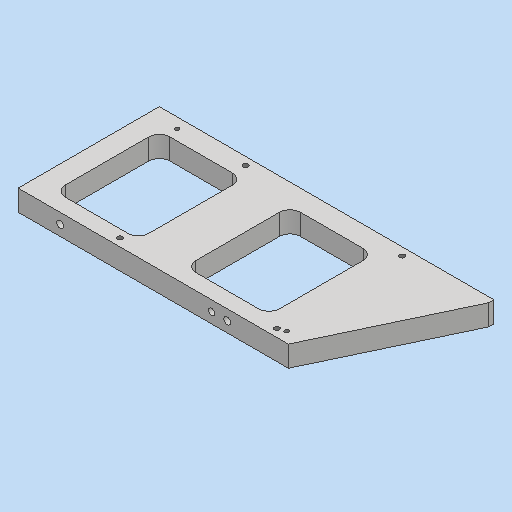
# Autodesk Inventor part: MM0948AN100_G01_155
Saved by Autodesk Inventor 2023.3 (Build 273359000, 359)
## iProperties
Part Number: MM0948AN100_G01_155
Material: 1.2842 90MnCrV8
Description: =<RBPARTNOTITLE2>
Document SubType Name: Modeling
Designer: ric7an
Mass: 3629.61 g
Surface Area: 811.162 cm^2
Volume: 462.37 cm^3
Density: 7.85 g/cm^3
Appearance: silber AnP
Created: 2023-03-23
RBDOCUMENTTYPE: DRF
RBDOCUMENTVERSION: 00
RBDRAWINGMAINSCALE: 1:1
RBDRAWINGMISSINGSPEC: --
RBDRAWINGVOLUME: --
RBGBEDGESIN1: +0,5
RBGBEDGESIN2: +0,2
RBGBEDGESOUT1: -0,3
RBGBEDGESOUT2: -0,1
RBMATERIAL: =<Material>
RBMATMEETS: --
RBMATNO: =<Part Number>
RBPARTMADEOF: 20 x 135 x 326,5 (FM)
RBPARTNO: SIEHE MNR
RBPARTNOTITLE1: manufactured part
RBPARTNOTITLE2: Anfertigungsteil
RBPARTSAFETYINDICATOR: --
RBSURFACE: chemically nickel-coated
RBSURFACE2: chem. vernickelt
RBZEDGESNORM: ISO13715:2002-06
RBZGENDIMCLASS: m
RBZGENDIMNORM: ISO 2768-1:1989-11
RBZGENGEOCLASS: H
RBZGENGEONORM: ISO 2768-2:1989-11
RBZSURFACENORM: ISO13D2:2002-02
RBZTOLERANCENORM: ISO 14405-1:2010-12
AnP_Material: =<Material>
AnP_TemplVers: 20190222
AnP_Kategorie: 1
MaxAbmaße: 20 x 135 x 326,5 (FM)
AnP_Kommentar_aktuell: =<Comments>
AnP_Material_aktuell: =<Material>
Author: FH/Wi
Keywords: =<RBPARTMADEOF>
Comments: =<RBSURFACE2>
Revision Number: 01
Autodesk Inventor part; units mm, degrees
ref_plane "YZ Plane" through (0, 0, 0) normal (1, 0, 0) x (0, 1, 0)
ref_plane "XZ Plane" through (0, 0, 0) normal (0, 1, 0) x (-1, 0, 0)
ref_plane "XY Plane" through (0, 0, 0) normal (0, 0, 1) x (1, 0, 0)
sketch "Skizze1" plane through (0, 0, 0) normal (0, 0, 1) x (1, 0, 0)
  line L0 (-160, 135) -> (160, 135)
  line L1 (160, 135) -> (160, 0)
  line L2 (160, 0) -> (-160, 0)
  line L3 (-160, 0) -> (-160, 135)
  line L4 (0, 162) -> (0, -27) projected
  line L5 (-224, 0) -> (224, 0) projected
  point P0 (0, 0)
  dimension "d0" = 135
  dimension "d1" = 320
  constraints: 8 end point, 2 parallel, 1 collinear, 1 horizontal, 1 perpendicular, 1 other
  measures "d0" distance of L0.end L1.end
  measures "d1" distance of L0.start L0.end
extrude "Extrusion1" add sketch "Skizze1" along normal mid plane 20
sketch "Skizze2" plane through (-160, 135, 10) normal (0, 1, 0) x (1, 0, 0)
  line L0 (160, 24) -> (160, -4) projected
  line L1 (384, 10) -> (-64, 10) projected
  line L2 (320, 0) -> (320, 20) projected
  line L3 (0, 20) -> (0, 0) projected
  point P0 (160, 10)
  point P1 (160, 10)
  point P2 (300, 10)
  dimension "d4" = 140
  dimension "d106" = 20
  constraints: 1 midpoint, 1 point on line
  measures "d4" distance of point (300, 10) point (160, 10)
  measures "d106" distance from line of L2 point (300, 10)
hole "Bohrung1" at (0, 135, 0) at (140, 135, 0) direction (0, -1, 0) diameter 4.917 depth 17.1 tip angle 118 thread size "M6x1" designation "M6" class "6H" standard "ISO Metric profile"
sketch "Skizze3" plane through (0, 0, 10) normal (0, 0, 1) x (1, 0, 0)
  line L0 (-15, 115) -> (65, 115)
  line L1 (65, 115) -> (65, 15)
  line L2 (65, 15) -> (-15, 15)
  line L3 (-15, 15) -> (-15, 115)
  line L4 (-160, 0) -> (160, 0) projected
  line L5 (-228.55, 0) -> (228.55, 0) projected
  line L6 (160, 0) -> (160, 135) projected
  line L7 (-160, 135) -> (-160, 0) projected
  line L8 (25, 115) -> (25, 15) construction
  line L9 (-140, 115) -> (-60, 115)
  line L10 (-60, 115) -> (-60, 15)
  line L11 (-60, 15) -> (-140, 15)
  line L12 (-140, 15) -> (-140, 115)
  line L13 (-100, 115) -> (-100, 15) construction
  point P0 (0, 0)
  dimension "d14" = 80
  dimension "d28" = 100
  dimension "d29" = 15
  dimension "d74" = 100
  dimension "d75" = 80
  dimension "d100" = 125
  dimension "d107" = 95
  constraints: 20 end point, 4 midpoint, 4 parallel, 2 horizontal, 2 perpendicular, 1 collinear
  measures "d14" distance of L0.start L0.end
  measures "d28" distance of L0.end L1.end
  measures "d29" distance between parallel lines of L4 L2
  measures "d74" distance of L9.end L10.end
  measures "d75" distance of L9.start L9.end
  measures "d100" distance between parallel lines of L3 L12
  measures "d107" distance between parallel lines of L6 L1
extrude "Extrusion2" cut sketch "Skizze3" against normal through all
sketch "Skizze4" plane through (-161.5, 15, 10) normal (0, -1, 0) x (1, 0, 0)
  line L0 (-62.5, -10) -> (385.5, -10) projected
  line L1 (226.5, 0) -> (146.5, 0) projected
  line L2 (21.5, -20) -> (101.5, -20) projected
  line L3 (21.5, 0) -> (21.5, -20) projected
  line L4 (101.5, 0) -> (21.5, 0) projected
  line L5 (101.5, 0) -> (101.5, -20) projected
  line L6 (321.5, 0) -> (321.5, -20) projected
  point P0 (161.5, -10)
  point P1 (201.5, -10)
  point P2 (41.5, -10)
  dimension "d109" = 160
  dimension "d110" = 120
  constraints: 2 point on line
  measures "d109" distance of point (201.5, -10) point (41.5, -10)
  measures "d110" distance from line of point (201.5, -10) L6
hole "Bohrung2" at (40, 15, 0) at (-120, 15, 0) direction (0, -1, 0) diameter 6.6 end through all clearance for "Innensechskant-Senkkopfschraube ISO 10642" size "M6" standard "ISO"
fillet "Rundung1" radius 10 8 edges at (-15, 115, 0) (65, 115, 0) (65, 15, 0) (-15, 15, 0) (-140, 15, 0) (-60, 15, 0) (-60, 115, 0) (-140, 115, 0)
sketch "Skizze8" plane through (0, 0, -10) normal (0, 0, -1) x (-1, 0, 0)
  line L0 (-160, 0) -> (160, 0) projected
  line L1 (-160, 135) -> (-160, 0) projected
  line L2 (160, 0) -> (160, 135) projected
  point P0 (-87, 10)
  point P1 (133, 125)
  dimension "d58" = 220
  dimension "d69" = 10
  dimension "d70" = 115
  dimension "d108" = 73
  measures "d58" horizontal distance of point (133, 125) point (-87, 10)
  measures "d69" distance from line of L0 point (-87, 10)
  measures "d70" vertical distance of point (133, 125) point (-87, 10)
  measures "d108" distance from line of point (-87, 10) L1
hole "Bohrung4" at (87, 10, -10) at (-133, 125, -10) direction (0, 0, 1) diameter 4.134 end through all thread size "M5x0.8" designation "M5" class "6H" standard "ISO Metric profile"
sketch "Skizze9" plane through (0, 0, -10) normal (0, 0, -1) x (-1, 0, 0)
  circle A0 centre (-87, 10) radius 2.067 projected
  circle A1 centre (133, 125) radius 2.067 projected
  line L0 (15, 105) -> (15, 25) projected
  line L1 (5, 15) -> (-55, 15) projected
  line L2 (-65, 25) -> (-65, 105) projected
  line L3 (-55, 115) -> (5, 115) projected
  line L4 (160, 135) -> (-160, 135) projected
  line L5 (-160, 135) -> (-160, 0) projected
  line L6 (-160, 0) -> (160, 0) projected
  line L7 (160, 0) -> (160, 135) projected
  arc A2 (-55, 115) -> (-65, 105) centre (-55, 105) ccw projected
  arc A3 (15, 105) -> (5, 115) centre (5, 105) ccw projected
  arc A4 (5, 15) -> (15, 25) centre (5, 25) ccw projected
  arc A5 (-65, 25) -> (-55, 15) centre (-55, 25) ccw projected
  line L8 (-98.5, 0) -> (-160, 130)
  point P0 (0, 0)
  dimension "d80" = 5
  dimension "d102" = 258.5
  constraints: 2 end point, 2 point on line
  measures "d80" distance from line of L4 L8.end
  measures "d102" distance from line of L7 L8.start
extrude "Extrusion5" cut sketch "Skizze9" against normal through all contours L8 L6 L5
sketch "Skizze10" plane through (-160, 0, -10) normal (0, -1, 0) x (1, 0, 0)
  circle A0 centre (200, 10) radius 3.3 projected
  point P0 (160, 10)
  point P1 (185, 10)
  dimension "d82" = 15
  constraints: 1 horizontal alignment
  measures "d82" distance of A0.centre point (185, 10)
hole "Bohrung5" at (25, 0, 0) direction (0, 1, 0) diameter 6 depth 15
sketch "Skizze11" plane through (-160, 135, 10) normal (0, 1, 0) x (1, 0, 0)
  line L0 (384, 10) -> (-64, 10) projected
  line L1 (320, 0) -> (320, 20) projected
  circle A0 centre (160, 10) radius 2.4585 projected
  circle A1 centre (300, 10) radius 2.4585 projected
  point P0 (288, 10)
  point P1 (148, 10)
  dimension "d103" = 12
  dimension "d104" = 12
  constraints: 2 point on line
  measures "d103" distance of A0.centre point (148, 10)
  measures "d104" distance of A1.centre point (288, 10)
hole "Bohrung6" at (128, 135, 0) at (-12, 135, 0) direction (0, -1, 0) diameter 6 depth 16 tip angle 118
sketch "Skizze12" plane through (0, 0, -10) normal (0, 0, -1) x (-1, 0, 0)
  line L0 (160, 135) -> (-160, 135) projected
  line L1 (-160, 135) -> (-160, 130) projected
  point P0 (0, 0)
  point P1 (-80, 127.5)
  point P2 (70, 127.5)
  point P3 (70, 7.5)
  point P4 (-80, 7.5)
  dimension "d111" = 150
  dimension "d112" = 120
  dimension "d113" = 7.5
  dimension "d114" = 80
  constraints: 2 horizontal alignment, 2 vertical alignment
  measures "d111" distance of point (70, 127.5) point (-80, 127.5)
  measures "d112" distance of point (70, 7.5) point (70, 127.5)
  measures "d113" distance from line of L0 point (70, 127.5)
  measures "d114" distance from line of point (-80, 127.5) L1
hole "Bohrung7" at (80, 127.5, -10) at (-70, 127.5, -10) at (-70, 7.5, -10) at (80, 7.5, -10) direction (0, 0, 1) diameter 4.917 end through all thread size "M6x1" designation "M6" class "6H" standard "ISO Metric profile"
equation "\"d74\" = d28"
equation "\"d75\" = d14"
